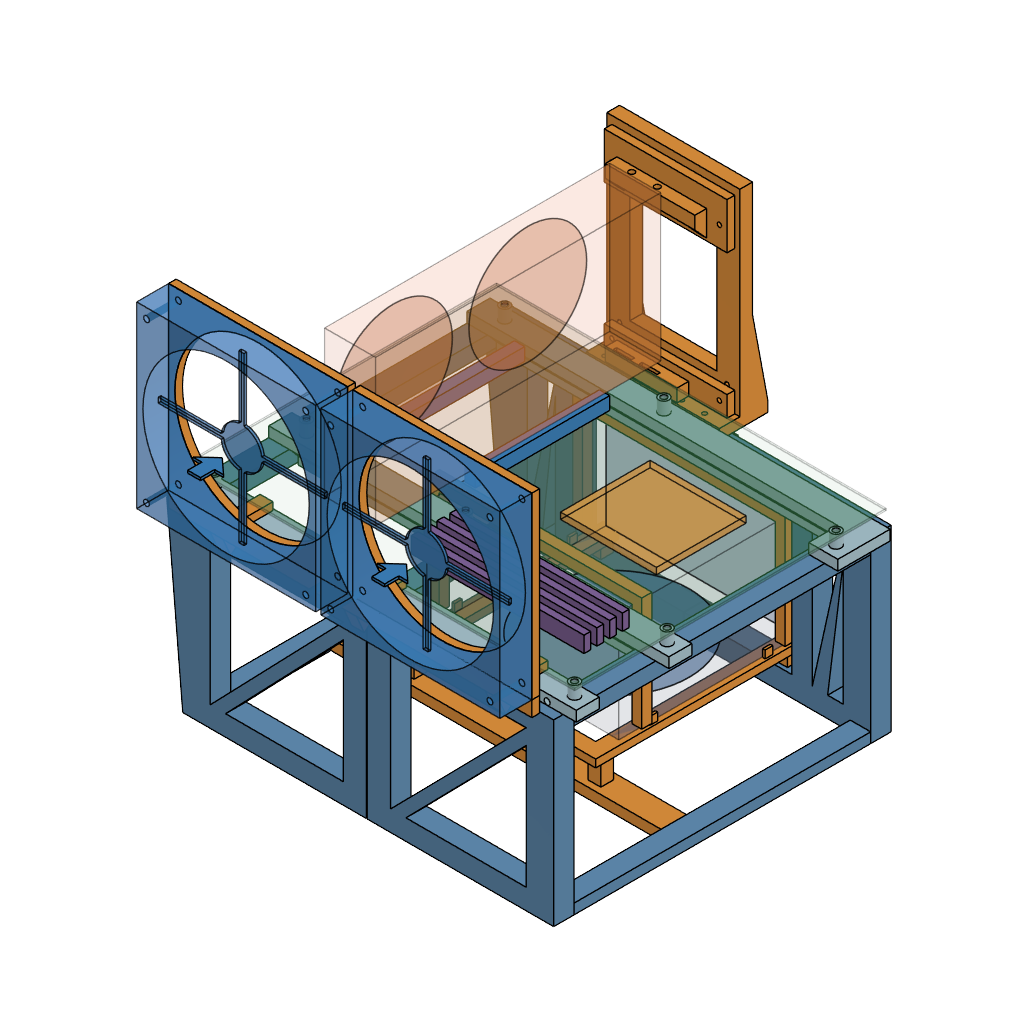
ATX_Desk_v08_layout (Autodesk Fusion 360 design; units mm, degrees)
part number: 2026-10-20-23-59-44-209
part number: 2026-10-20-23-59-51-964
part number: 2026-10-20-23-59-56-069
part number: 2026-10-21-00-00-01-103
part number: 2026-10-21-00-00-46-426
part number: 2026-10-21-00-00-56-981
part number: 2026-10-21-00-01-04-262
part number: 2026-10-21-00-01-12-035
part number: 2026-10-21-00-01-25-487
part number: 2026-10-21-00-01-28-371
part number: 2026-10-21-00-01-43-062
part number: 2026-10-21-00-01-46-190
part number: 2026-10-21-00-02-02-158
part number: 2026-10-21-00-02-04-809
part number: 2026-10-21-00-02-14-600
part number: 2026-10-21-00-02-17-363
part number: 2026-10-21-00-02-20-116
part number: 2026-10-21-00-02-27-737
part number: 2026-10-21-07-09-29-613
part number: 2026-10-21-07-09-34-403
part number: 2026-10-21-07-09-39-275
part number: 2026-10-21-07-09-42-839
part number: 2026-10-21-07-09-45-395
part number: 2026-10-21-07-15-53-070
part number: 2026-10-21-07-16-00-584
part number: 2026-10-21-07-16-09-777
part number: 2026-10-21-07-16-14-749
part number: 2026-10-21-07-16-20-002
part number: 2026-10-21-07-16-22-889
part number: 2026-10-21-07-16-25-682
part number: 2026-10-21-07-16-28-506
part number: 2026-10-21-07-23-00-483
part number: 2026-10-21-07-23-51-474
part number: 2026-10-21-07-24-11-185
part number: 2026-10-21-07-39-56-923
part number: 2026-10-21-07-40-00-193
part number: 2026-10-21-07-40-45-771
part number: 2026-10-21-07-40-57-754
Autodesk Fusion 360 part; units mm, degrees
(part 1 of 2)
ref_plane "工作平面1" through (0, 0, 190) normal (0, 0, 1) x (1, 0, 0) in component "03_FRONT_MOTHERBOARD_BEAM"
sketch "草图1" plane through (0, 0, 190) normal (0, 0, 1) x (1, 0, 0) in component "03_FRONT_MOTHERBOARD_BEAM"
  line L0 (-4, -2.65) -> (308.8, -2.65)
  line L1 (308.8, -2.65) -> (308.8, 15.35)
  line L2 (308.8, 15.35) -> (-4, 15.35)
  line L3 (-4, 15.35) -> (-4, -2.65)
extrude "Upper beam flange" add sketch "草图1" along normal blind 8 makes body 1 in component "03_FRONT_MOTHERBOARD_BEAM"
ref_plane "工作平面2" through (0, 0, 178) normal (0, 0, 1) x (1, 0, 0) in component "03_FRONT_MOTHERBOARD_BEAM"
sketch "草图2" plane through (0, 0, 178) normal (0, 0, 1) x (1, 0, 0) in component "03_FRONT_MOTHERBOARD_BEAM"
  line L0 (14, 2.35) -> (281.45, 2.35)
  line L1 (281.45, 2.35) -> (281.45, 10.35)
  line L2 (281.45, 10.35) -> (14, 10.35)
  line L3 (14, 10.35) -> (14, 2.35)
extrude "Underside rib" add sketch "草图2" along normal blind 12 bodies 1 in component "03_FRONT_MOTHERBOARD_BEAM"
ref_plane "工作平面3" through (14, 0, 0) normal (1, 0, 0) x (0, 1, 0) in component "03_FRONT_MOTHERBOARD_BEAM"
sketch "草图3" plane through (14, 0, 0) normal (1, 0, 0) x (0, 0, -1) in component "03_FRONT_MOTHERBOARD_BEAM"
  line L0 (-184, 2.35) -> (-184, 10.35)
  line L1 (-184, 10.35) -> (-190, 15.35)
  line L2 (-190, 15.35) -> (-190, -2.65)
  line L3 (-190, -2.65) -> (-184, 2.35)
extrude "Printable rib transition" add sketch "草图3" along normal blind 267.45 bodies 1 in component "03_FRONT_MOTHERBOARD_BEAM"
ref_plane "工作平面4" through (0, 0, 198) normal (0, 0, 1) x (1, 0, 0) in component "03_FRONT_MOTHERBOARD_BEAM"
sketch "草图4" plane through (0, 0, 198) normal (0, 0, 1) x (1, 0, 0) in component "03_FRONT_MOTHERBOARD_BEAM"
  circle A0 centre (16.51, 6.35) radius 4
extrude "Motherboard mount 7" add sketch "草图4" along normal blind 10 bodies 1 in component "03_FRONT_MOTHERBOARD_BEAM"
ref_plane "工作平面5" through (0, 0, 203.1) normal (0, 0, 1) x (1, 0, 0) in component "03_FRONT_MOTHERBOARD_BEAM"
sketch "草图5" plane through (0, 0, 203.1) normal (0, 0, 1) x (1, 0, 0) in component "03_FRONT_MOTHERBOARD_BEAM"
  circle A0 centre (16.51, 6.35) radius 2.35
extrude "M3 insert pocket 7" cut sketch "草图5" along normal blind 4.9 bodies 1 in component "03_FRONT_MOTHERBOARD_BEAM"
ref_plane "工作平面6" through (0, 0, 198) normal (0, 0, 1) x (1, 0, 0) in component "03_FRONT_MOTHERBOARD_BEAM"
sketch "草图6" plane through (0, 0, 198) normal (0, 0, 1) x (1, 0, 0) in component "03_FRONT_MOTHERBOARD_BEAM"
  circle A0 centre (140.97, 6.35) radius 4
extrude "Motherboard mount 8" add sketch "草图6" along normal blind 10 bodies 1 in component "03_FRONT_MOTHERBOARD_BEAM"
ref_plane "工作平面7" through (0, 0, 203.1) normal (0, 0, 1) x (1, 0, 0) in component "03_FRONT_MOTHERBOARD_BEAM"
sketch "草图7" plane through (0, 0, 203.1) normal (0, 0, 1) x (1, 0, 0) in component "03_FRONT_MOTHERBOARD_BEAM"
  circle A0 centre (140.97, 6.35) radius 2.35
extrude "M3 insert pocket 8" cut sketch "草图7" along normal blind 4.9 bodies 1 in component "03_FRONT_MOTHERBOARD_BEAM"
ref_plane "工作平面8" through (0, 0, 198) normal (0, 0, 1) x (1, 0, 0) in component "03_FRONT_MOTHERBOARD_BEAM"
sketch "草图8" plane through (0, 0, 198) normal (0, 0, 1) x (1, 0, 0) in component "03_FRONT_MOTHERBOARD_BEAM"
  circle A0 centre (298.45, 6.35) radius 4
extrude "Motherboard mount 9" add sketch "草图8" along normal blind 10 bodies 1 in component "03_FRONT_MOTHERBOARD_BEAM"
ref_plane "工作平面9" through (0, 0, 203.1) normal (0, 0, 1) x (1, 0, 0) in component "03_FRONT_MOTHERBOARD_BEAM"
sketch "草图9" plane through (0, 0, 203.1) normal (0, 0, 1) x (1, 0, 0) in component "03_FRONT_MOTHERBOARD_BEAM"
  circle A0 centre (298.45, 6.35) radius 2.35
extrude "M3 insert pocket 9" cut sketch "草图9" along normal blind 4.9 bodies 1 in component "03_FRONT_MOTHERBOARD_BEAM"
ref_plane "工作平面1" through (0, 0, 190) normal (0, 0, 1) x (1, 0, 0) in component "03_MID_MOTHERBOARD_BEAM"
sketch "草图1 (2)" plane through (0, 0, 190) normal (0, 0, 1) x (1, 0, 0) in component "03_MID_MOTHERBOARD_BEAM"
  line L0 (-4, 69.74) -> (308.8, 69.74)
  line L1 (308.8, 69.74) -> (308.8, 87.74)
  line L2 (308.8, 87.74) -> (-4, 87.74)
  line L3 (-4, 87.74) -> (-4, 69.74)
extrude "Upper beam flange'" add sketch "草图1 (2)" along normal blind 8 separate body makes body 2 in component "03_MID_MOTHERBOARD_BEAM"
ref_plane "工作平面2" through (0, 0, 178) normal (0, 0, 1) x (1, 0, 0) in component "03_MID_MOTHERBOARD_BEAM"
sketch "草图2 (2)" plane through (0, 0, 178) normal (0, 0, 1) x (1, 0, 0) in component "03_MID_MOTHERBOARD_BEAM"
  line L0 (14, 74.74) -> (281.45, 74.74)
  line L1 (281.45, 74.74) -> (281.45, 82.74)
  line L2 (281.45, 82.74) -> (14, 82.74)
  line L3 (14, 82.74) -> (14, 74.74)
extrude "Underside rib'" add sketch "草图2 (2)" along normal blind 12 bodies 2 in component "03_MID_MOTHERBOARD_BEAM"
ref_plane "工作平面3" through (14, 0, 0) normal (1, 0, 0) x (0, 1, 0) in component "03_MID_MOTHERBOARD_BEAM"
sketch "草图3 (2)" plane through (14, 0, 0) normal (1, 0, 0) x (0, 0, -1) in component "03_MID_MOTHERBOARD_BEAM"
  line L0 (-184, 74.74) -> (-184, 82.74)
  line L1 (-184, 82.74) -> (-190, 87.74)
  line L2 (-190, 87.74) -> (-190, 69.74)
  line L3 (-190, 69.74) -> (-184, 74.74)
extrude "Printable rib transition'" add sketch "草图3 (2)" along normal blind 267.45 bodies 2 in component "03_MID_MOTHERBOARD_BEAM"
ref_plane "工作平面4" through (0, 0, 198) normal (0, 0, 1) x (1, 0, 0) in component "03_MID_MOTHERBOARD_BEAM"
sketch "草图4 (2)" plane through (0, 0, 198) normal (0, 0, 1) x (1, 0, 0) in component "03_MID_MOTHERBOARD_BEAM"
  circle A0 centre (16.51, 78.74) radius 4
extrude "Motherboard mount 4" add sketch "草图4 (2)" along normal blind 10 bodies 2 in component "03_MID_MOTHERBOARD_BEAM"
ref_plane "工作平面5" through (0, 0, 203.1) normal (0, 0, 1) x (1, 0, 0) in component "03_MID_MOTHERBOARD_BEAM"
sketch "草图5 (2)" plane through (0, 0, 203.1) normal (0, 0, 1) x (1, 0, 0) in component "03_MID_MOTHERBOARD_BEAM"
  circle A0 centre (16.51, 78.74) radius 2.35
extrude "M3 insert pocket 4" cut sketch "草图5 (2)" along normal blind 4.9 bodies 2 in component "03_MID_MOTHERBOARD_BEAM"
ref_plane "工作平面6" through (0, 0, 198) normal (0, 0, 1) x (1, 0, 0) in component "03_MID_MOTHERBOARD_BEAM"
sketch "草图6 (2)" plane through (0, 0, 198) normal (0, 0, 1) x (1, 0, 0) in component "03_MID_MOTHERBOARD_BEAM"
  circle A0 centre (140.97, 78.74) radius 4
extrude "Motherboard mount 5" add sketch "草图6 (2)" along normal blind 10 bodies 2 in component "03_MID_MOTHERBOARD_BEAM"
ref_plane "工作平面7" through (0, 0, 203.1) normal (0, 0, 1) x (1, 0, 0) in component "03_MID_MOTHERBOARD_BEAM"
sketch "草图7 (2)" plane through (0, 0, 203.1) normal (0, 0, 1) x (1, 0, 0) in component "03_MID_MOTHERBOARD_BEAM"
  circle A0 centre (140.97, 78.74) radius 2.35
extrude "M3 insert pocket 5" cut sketch "草图7 (2)" along normal blind 4.9 bodies 2 in component "03_MID_MOTHERBOARD_BEAM"
ref_plane "工作平面8" through (0, 0, 198) normal (0, 0, 1) x (1, 0, 0) in component "03_MID_MOTHERBOARD_BEAM"
sketch "草图8 (2)" plane through (0, 0, 198) normal (0, 0, 1) x (1, 0, 0) in component "03_MID_MOTHERBOARD_BEAM"
  circle A0 centre (298.45, 78.74) radius 4
extrude "Motherboard mount 6" add sketch "草图8 (2)" along normal blind 10 bodies 2 in component "03_MID_MOTHERBOARD_BEAM"
ref_plane "工作平面9" through (0, 0, 203.1) normal (0, 0, 1) x (1, 0, 0) in component "03_MID_MOTHERBOARD_BEAM"
sketch "草图9 (2)" plane through (0, 0, 203.1) normal (0, 0, 1) x (1, 0, 0) in component "03_MID_MOTHERBOARD_BEAM"
  circle A0 centre (298.45, 78.74) radius 2.35
extrude "M3 insert pocket 6" cut sketch "草图9 (2)" along normal blind 4.9 bodies 2 in component "03_MID_MOTHERBOARD_BEAM"
ref_plane "工作平面1" through (0, 0, 190) normal (0, 0, 1) x (1, 0, 0) in component "03_REAR_MOTHERBOARD_BEAM"
sketch "草图1 (3)" plane through (0, 0, 190) normal (0, 0, 1) x (1, 0, 0) in component "03_REAR_MOTHERBOARD_BEAM"
  line L0 (-4, 224.68) -> (308.8, 224.68)
  line L1 (308.8, 224.68) -> (308.8, 242.68)
  line L2 (308.8, 242.68) -> (-4, 242.68)
  line L3 (-4, 242.68) -> (-4, 224.68)
extrude "Upper beam flange''" add sketch "草图1 (3)" along normal blind 8 separate body makes body 3 in component "03_REAR_MOTHERBOARD_BEAM"
ref_plane "工作平面2" through (0, 0, 178) normal (0, 0, 1) x (1, 0, 0) in component "03_REAR_MOTHERBOARD_BEAM"
sketch "草图2 (3)" plane through (0, 0, 178) normal (0, 0, 1) x (1, 0, 0) in component "03_REAR_MOTHERBOARD_BEAM"
  line L0 (14, 229.68) -> (281.45, 229.68)
  line L1 (281.45, 229.68) -> (281.45, 237.68)
  line L2 (281.45, 237.68) -> (14, 237.68)
  line L3 (14, 237.68) -> (14, 229.68)
extrude "Underside rib''" add sketch "草图2 (3)" along normal blind 12 bodies 3 in component "03_REAR_MOTHERBOARD_BEAM"
ref_plane "工作平面3" through (14, 0, 0) normal (1, 0, 0) x (0, 1, 0) in component "03_REAR_MOTHERBOARD_BEAM"
sketch "草图3 (3)" plane through (14, 0, 0) normal (1, 0, 0) x (0, 0, -1) in component "03_REAR_MOTHERBOARD_BEAM"
  line L0 (-184, 229.68) -> (-184, 237.68)
  line L1 (-184, 237.68) -> (-190, 242.68)
  line L2 (-190, 242.68) -> (-190, 224.68)
  line L3 (-190, 224.68) -> (-184, 229.68)
extrude "Printable rib transition''" add sketch "草图3 (3)" along normal blind 267.45 bodies 3 in component "03_REAR_MOTHERBOARD_BEAM"
ref_plane "工作平面4" through (0, 0, 190) normal (0, 0, 1) x (1, 0, 0) in component "03_REAR_MOTHERBOARD_BEAM"
sketch "草图4 (3)" plane through (0, 0, 190) normal (0, 0, 1) x (1, 0, 0) in component "03_REAR_MOTHERBOARD_BEAM"
  line L0 (286, 201.82) -> (308.8, 201.82)
  line L1 (308.8, 201.82) -> (308.8, 233.68)
  line L2 (308.8, 233.68) -> (286, 233.68)
  line L3 (286, 233.68) -> (286, 201.82)
extrude "Staggered hole 3 pad" add sketch "草图4 (3)" along normal blind 8 bodies 3 in component "03_REAR_MOTHERBOARD_BEAM"
ref_plane "工作平面5" through (0, 0, 198) normal (0, 0, 1) x (1, 0, 0) in component "03_REAR_MOTHERBOARD_BEAM"
sketch "草图5 (3)" plane through (0, 0, 198) normal (0, 0, 1) x (1, 0, 0) in component "03_REAR_MOTHERBOARD_BEAM"
  circle A0 centre (16.51, 233.68) radius 4
extrude "Motherboard mount 1" add sketch "草图5 (3)" along normal blind 10 bodies 3 in component "03_REAR_MOTHERBOARD_BEAM"
ref_plane "工作平面6" through (0, 0, 203.1) normal (0, 0, 1) x (1, 0, 0) in component "03_REAR_MOTHERBOARD_BEAM"
sketch "草图6 (3)" plane through (0, 0, 203.1) normal (0, 0, 1) x (1, 0, 0) in component "03_REAR_MOTHERBOARD_BEAM"
  circle A0 centre (16.51, 233.68) radius 2.35
extrude "M3 insert pocket 1" cut sketch "草图6 (3)" along normal blind 4.9 bodies 3 in component "03_REAR_MOTHERBOARD_BEAM"
ref_plane "工作平面7" through (0, 0, 198) normal (0, 0, 1) x (1, 0, 0) in component "03_REAR_MOTHERBOARD_BEAM"
sketch "草图7 (3)" plane through (0, 0, 198) normal (0, 0, 1) x (1, 0, 0) in component "03_REAR_MOTHERBOARD_BEAM"
  circle A0 centre (140.97, 233.68) radius 4
extrude "Motherboard mount 2" add sketch "草图7 (3)" along normal blind 10 bodies 3 in component "03_REAR_MOTHERBOARD_BEAM"
ref_plane "工作平面8" through (0, 0, 203.1) normal (0, 0, 1) x (1, 0, 0) in component "03_REAR_MOTHERBOARD_BEAM"
sketch "草图8 (3)" plane through (0, 0, 203.1) normal (0, 0, 1) x (1, 0, 0) in component "03_REAR_MOTHERBOARD_BEAM"
  circle A0 centre (140.97, 233.68) radius 2.35
extrude "M3 insert pocket 2" cut sketch "草图8 (3)" along normal blind 4.9 bodies 3 in component "03_REAR_MOTHERBOARD_BEAM"
ref_plane "工作平面9" through (0, 0, 198) normal (0, 0, 1) x (1, 0, 0) in component "03_REAR_MOTHERBOARD_BEAM"
sketch "草图9 (3)" plane through (0, 0, 198) normal (0, 0, 1) x (1, 0, 0) in component "03_REAR_MOTHERBOARD_BEAM"
  circle A0 centre (298.45, 210.82) radius 4
extrude "Motherboard mount 3" add sketch "草图9 (3)" along normal blind 10 bodies 3 in component "03_REAR_MOTHERBOARD_BEAM"
ref_plane "工作平面10" through (0, 0, 203.1) normal (0, 0, 1) x (1, 0, 0) in component "03_REAR_MOTHERBOARD_BEAM"
sketch "草图10" plane through (0, 0, 203.1) normal (0, 0, 1) x (1, 0, 0) in component "03_REAR_MOTHERBOARD_BEAM"
  circle A0 centre (298.45, 210.82) radius 2.35
extrude "M3 insert pocket 3" cut sketch "草图10" along normal blind 4.9 bodies 3 in component "03_REAR_MOTHERBOARD_BEAM"
ref_plane "工作平面1" through (0, 0, 198) normal (0, 0, 1) x (1, 0, 0) in component "09_FRONT_DUAL_FAN_CARRIER"
sketch "草图1 (4)" plane through (0, 0, 198) normal (0, 0, 1) x (1, 0, 0) in component "09_FRONT_DUAL_FAN_CARRIER"
  line L0 (12.4, -25) -> (296.4, -25)
  line L1 (296.4, -25) -> (296.4, -19)
  line L2 (296.4, -19) -> (12.4, -19)
  line L3 (12.4, -19) -> (12.4, -25)
extrude "Common 284 mm wide fan carrier" add sketch "草图1 (4)" along normal blind 12 separate body makes body 4 in component "09_FRONT_DUAL_FAN_CARRIER"
ref_plane "工作平面2" through (0, 0, 198) normal (0, 0, 1) x (1, 0, 0) in component "09_FRONT_DUAL_FAN_CARRIER"
sketch "草图2 (4)" plane through (0, 0, 198) normal (0, 0, 1) x (1, 0, 0) in component "09_FRONT_DUAL_FAN_CARRIER"
  line L0 (45, -19) -> (55, -19)
  line L1 (55, -19) -> (55, 14)
  line L2 (55, 14) -> (45, 14)
  line L3 (45, 14) -> (45, -19)
extrude "Fan carrier arm onto front beam" add sketch "草图2 (4)" along normal blind 6 bodies 4 in component "09_FRONT_DUAL_FAN_CARRIER"
ref_plane "工作平面3" through (45, 0, 0) normal (1, 0, 0) x (0, 1, 0) in component "09_FRONT_DUAL_FAN_CARRIER"
sketch "草图3 (4)" plane through (45, 0, 0) normal (1, 0, 0) x (0, 0, -1) in component "09_FRONT_DUAL_FAN_CARRIER"
  line L0 (-198, -25) -> (-184, -19)
  line L1 (-184, -19) -> (-198, -2.65)
  line L2 (-198, -2.65) -> (-198, -25)
extrude "Fan carrier arm gusset" add sketch "草图3 (4)" along normal blind 10 bodies 4 in component "09_FRONT_DUAL_FAN_CARRIER"
ref_plane "工作平面4" through (0, 0, 198) normal (0, 0, 1) x (1, 0, 0) in component "09_FRONT_DUAL_FAN_CARRIER"
sketch "草图4 (4)" plane through (0, 0, 198) normal (0, 0, 1) x (1, 0, 0) in component "09_FRONT_DUAL_FAN_CARRIER"
  line L0 (149.4, -19) -> (159.4, -19)
  line L1 (159.4, -19) -> (159.4, 14)
  line L2 (159.4, 14) -> (149.4, 14)
  line L3 (149.4, 14) -> (149.4, -19)
extrude "Fan carrier arm onto front beam (1)" add sketch "草图4 (4)" along normal blind 6 bodies 4 in component "09_FRONT_DUAL_FAN_CARRIER"
ref_plane "工作平面5" through (149.4, 0, 0) normal (1, 0, 0) x (0, 1, 0) in component "09_FRONT_DUAL_FAN_CARRIER"
sketch "草图5 (4)" plane through (149.4, 0, 0) normal (1, 0, 0) x (0, 0, -1) in component "09_FRONT_DUAL_FAN_CARRIER"
  line L0 (-198, -25) -> (-184, -19)
  line L1 (-184, -19) -> (-198, -2.65)
  line L2 (-198, -2.65) -> (-198, -25)
extrude "Fan carrier arm gusset (1)" add sketch "草图5 (4)" along normal blind 10 bodies 4 in component "09_FRONT_DUAL_FAN_CARRIER"
ref_plane "工作平面6" through (0, 0, 198) normal (0, 0, 1) x (1, 0, 0) in component "09_FRONT_DUAL_FAN_CARRIER"
sketch "草图6 (4)" plane through (0, 0, 198) normal (0, 0, 1) x (1, 0, 0) in component "09_FRONT_DUAL_FAN_CARRIER"
  line L0 (260, -19) -> (270, -19)
  line L1 (270, -19) -> (270, 14)
  line L2 (270, 14) -> (260, 14)
  line L3 (260, 14) -> (260, -19)
extrude "Fan carrier arm onto front beam (2)" add sketch "草图6 (4)" along normal blind 6 bodies 4 in component "09_FRONT_DUAL_FAN_CARRIER"
ref_plane "工作平面7" through (260, 0, 0) normal (1, 0, 0) x (0, 1, 0) in component "09_FRONT_DUAL_FAN_CARRIER"
sketch "草图7 (4)" plane through (260, 0, 0) normal (1, 0, 0) x (0, 0, -1) in component "09_FRONT_DUAL_FAN_CARRIER"
  line L0 (-198, -25) -> (-184, -19)
  line L1 (-184, -19) -> (-198, -2.65)
  line L2 (-198, -2.65) -> (-198, -25)
extrude "Fan carrier arm gusset (2)" add sketch "草图7 (4)" along normal blind 10 bodies 4 in component "09_FRONT_DUAL_FAN_CARRIER"
ref_plane "工作平面1" through (0, 25, 0) normal (0, 1, 0) x (0, 0, 1) in component "10_GPU_140_FAN_MOUNT"
sketch "草图1 (5)" plane through (0, 25, 0) normal (0, 1, 0) x (1, 0, 0) in component "10_GPU_140_FAN_MOUNT"
  line L0 (12.4, -210, -50) -> (152.4, -210, -50)
  line L1 (152.4, -210, -50) -> (152.4, -350, -50)
  line L2 (152.4, -350, -50) -> (12.4, -350, -50)
  line L3 (12.4, -350, -50) -> (12.4, -210, -50)
extrude "140 mm removable fan mounting frame" add sketch "草图1 (5)" along normal blind 6 separate body contours L0 L1 L2 L3 in plane through (0, -25, 0) normal (0, 1, 0) makes body 5 in component "10_GPU_140_FAN_MOUNT"
ref_plane "工作平面2" through (0, 25, 0) normal (0, 1, 0) x (0, 0, 1) in component "10_GPU_140_FAN_MOUNT"
sketch "草图2 (5)" plane through (0, 25, 0) normal (0, 1, 0) x (1, 0, 0) in component "10_GPU_140_FAN_MOUNT"
  circle A0 through (147.4, -280, -50) (49.9, -223.7083, -50) (49.9, -336.2917, -50)
extrude "Open airflow aperture" cut sketch "草图2 (5)" along normal blind 6 contours A0 in plane through (0, -25, 0) normal (0, 1, 0) bodies 5 in component "10_GPU_140_FAN_MOUNT"
ref_plane "工作平面3" through (0, 25, 0) normal (0, 1, 0) x (0, 0, 1) in component "10_GPU_140_FAN_MOUNT"
sketch "草图3 (5)" plane through (0, 25, 0) normal (0, 1, 0) x (1, 0, 0) in component "10_GPU_140_FAN_MOUNT"
  circle A0 through (22.4, -217.75, -50) (19.025, -215.8014, -50) (19.025, -219.6986, -50)
extrude "124.5 mm pitch fan fixing clearance" cut sketch "草图3 (5)" along normal blind 6 contours A0 in plane through (0, -25, 0) normal (0, 1, 0) bodies 5 in component "10_GPU_140_FAN_MOUNT"
ref_plane "工作平面4" through (0, 25, 0) normal (0, 1, 0) x (0, 0, 1) in component "10_GPU_140_FAN_MOUNT"
sketch "草图4 (5)" plane through (0, 25, 0) normal (0, 1, 0) x (1, 0, 0) in component "10_GPU_140_FAN_MOUNT"
  circle A0 through (22.4, -342.25, -50) (19.025, -340.3014, -50) (19.025, -344.1986, -50)
extrude "124.5 mm pitch fan fixing clearance (1)" cut sketch "草图4 (5)" along normal blind 6 contours A0 in plane through (0, -25, 0) normal (0, 1, 0) bodies 5 in component "10_GPU_140_FAN_MOUNT"
ref_plane "工作平面5" through (0, 25, 0) normal (0, 1, 0) x (0, 0, 1) in component "10_GPU_140_FAN_MOUNT"
sketch "草图5 (5)" plane through (0, 25, 0) normal (0, 1, 0) x (1, 0, 0) in component "10_GPU_140_FAN_MOUNT"
  circle A0 through (146.9, -217.75, -50) (143.525, -215.8014, -50) (143.525, -219.6986, -50)
extrude "124.5 mm pitch fan fixing clearance (2)" cut sketch "草图5 (5)" along normal blind 6 contours A0 in plane through (0, -25, 0) normal (0, 1, 0) bodies 5 in component "10_GPU_140_FAN_MOUNT"
ref_plane "工作平面6" through (0, 25, 0) normal (0, 1, 0) x (0, 0, 1) in component "10_GPU_140_FAN_MOUNT"
sketch "草图6 (5)" plane through (0, 25, 0) normal (0, 1, 0) x (1, 0, 0) in component "10_GPU_140_FAN_MOUNT"
  circle A0 through (146.9, -342.25, -50) (143.525, -340.3014, -50) (143.525, -344.1986, -50)
extrude "124.5 mm pitch fan fixing clearance (3)" cut sketch "草图6 (5)" along normal blind 6 contours A0 in plane through (0, -25, 0) normal (0, 1, 0) bodies 5 in component "10_GPU_140_FAN_MOUNT"
ref_plane "工作平面1" through (0, 25, 0) normal (0, 1, 0) x (0, 0, 1) in component "10_CPU_140_FAN_MOUNT"
sketch "草图1 (6)" plane through (0, 25, 0) normal (0, 1, 0) x (1, 0, 0) in component "10_CPU_140_FAN_MOUNT"
  line L0 (156.4, -210, -50) -> (296.4, -210, -50)
  line L1 (296.4, -210, -50) -> (296.4, -350, -50)
  line L2 (296.4, -350, -50) -> (156.4, -350, -50)
  line L3 (156.4, -350, -50) -> (156.4, -210, -50)
extrude "140 mm removable fan mounting frame'" add sketch "草图1 (6)" along normal blind 6 separate body contours L0 L1 L2 L3 in plane through (0, -25, 0) normal (0, 1, 0) makes body 6 in component "10_CPU_140_FAN_MOUNT"
ref_plane "工作平面2" through (0, 25, 0) normal (0, 1, 0) x (0, 0, 1) in component "10_CPU_140_FAN_MOUNT"
sketch "草图2 (6)" plane through (0, 25, 0) normal (0, 1, 0) x (1, 0, 0) in component "10_CPU_140_FAN_MOUNT"
  circle A0 through (291.4, -280, -50) (193.9, -223.7083, -50) (193.9, -336.2917, -50)
extrude "Open airflow aperture'" cut sketch "草图2 (6)" along normal blind 6 contours A0 in plane through (0, -25, 0) normal (0, 1, 0) bodies 6 in component "10_CPU_140_FAN_MOUNT"
ref_plane "工作平面3" through (0, 25, 0) normal (0, 1, 0) x (0, 0, 1) in component "10_CPU_140_FAN_MOUNT"
sketch "草图3 (6)" plane through (0, 25, 0) normal (0, 1, 0) x (1, 0, 0) in component "10_CPU_140_FAN_MOUNT"
  circle A0 through (166.4, -217.75, -50) (163.025, -215.8014, -50) (163.025, -219.6986, -50)
extrude "124.5 mm pitch fan fixing clearance'" cut sketch "草图3 (6)" along normal blind 6 contours A0 in plane through (0, -25, 0) normal (0, 1, 0) bodies 6 in component "10_CPU_140_FAN_MOUNT"
ref_plane "工作平面4" through (0, 25, 0) normal (0, 1, 0) x (0, 0, 1) in component "10_CPU_140_FAN_MOUNT"
sketch "草图4 (6)" plane through (0, 25, 0) normal (0, 1, 0) x (1, 0, 0) in component "10_CPU_140_FAN_MOUNT"
  circle A0 through (166.4, -342.25, -50) (163.025, -340.3014, -50) (163.025, -344.1986, -50)
extrude "124.5 mm pitch fan fixing clearance (1)'" cut sketch "草图4 (6)" along normal blind 6 contours A0 in plane through (0, -25, 0) normal (0, 1, 0) bodies 6 in component "10_CPU_140_FAN_MOUNT"
ref_plane "工作平面5" through (0, 25, 0) normal (0, 1, 0) x (0, 0, 1) in component "10_CPU_140_FAN_MOUNT"
sketch "草图5 (6)" plane through (0, 25, 0) normal (0, 1, 0) x (1, 0, 0) in component "10_CPU_140_FAN_MOUNT"
  circle A0 through (290.9, -217.75, -50) (287.525, -215.8014, -50) (287.525, -219.6986, -50)
extrude "124.5 mm pitch fan fixing clearance (2)'" cut sketch "草图5 (6)" along normal blind 6 contours A0 in plane through (0, -25, 0) normal (0, 1, 0) bodies 6 in component "10_CPU_140_FAN_MOUNT"
ref_plane "工作平面6" through (0, 25, 0) normal (0, 1, 0) x (0, 0, 1) in component "10_CPU_140_FAN_MOUNT"
sketch "草图6 (6)" plane through (0, 25, 0) normal (0, 1, 0) x (1, 0, 0) in component "10_CPU_140_FAN_MOUNT"
  circle A0 through (290.9, -342.25, -50) (287.525, -340.3014, -50) (287.525, -344.1986, -50)
extrude "124.5 mm pitch fan fixing clearance (3)'" cut sketch "草图6 (6)" along normal blind 6 contours A0 in plane through (0, -25, 0) normal (0, 1, 0) bodies 6 in component "10_CPU_140_FAN_MOUNT"
ref_plane "工作平面1" through (0, 50, 0) normal (0, 1, 0) x (0, 0, 1) in component "REF_CASE_FAN_GPU_140x140x25"
sketch "草图1 (7)" plane through (0, 50, 0) normal (0, 1, 0) x (1, 0, 0) in component "REF_CASE_FAN_GPU_140x140x25"
  line L0 (12.4, -210, -100) -> (152.4, -210, -100)
  line L1 (152.4, -210, -100) -> (152.4, -350, -100)
  line L2 (152.4, -350, -100) -> (12.4, -350, -100)
  line L3 (12.4, -350, -100) -> (12.4, -210, -100)
extrude "140x140x25 fan envelope" add sketch "草图1 (7)" along normal blind 25 separate body contours L0 L1 L2 L3 in plane through (0, -50, 0) normal (0, 1, 0) makes body 7 in component "REF_CASE_FAN_GPU_140x140x25"
ref_plane "工作平面2" through (0, 50, 0) normal (0, 1, 0) x (0, 0, 1) in component "REF_CASE_FAN_GPU_140x140x25"
sketch "草图2 (7)" plane through (0, 50, 0) normal (0, 1, 0) x (1, 0, 0) in component "REF_CASE_FAN_GPU_140x140x25"
  circle A0 through (147.4, -280, -100) (49.9, -223.7083, -100) (49.9, -336.2917, -100)
extrude "Rotor opening reference" cut sketch "草图2 (7)" along normal blind 25 contours A0 in plane through (0, -50, 0) normal (0, 1, 0) bodies 7 in component "REF_CASE_FAN_GPU_140x140x25"
ref_plane "工作平面3" through (0, 0, 278) normal (0, 0, 1) x (1, 0, 0) in component "REF_CASE_FAN_GPU_140x140x25"
sketch "草图3 (7)" plane through (0, 0, 278) normal (0, 0, 1) x (1, 0, 0) in component "REF_CASE_FAN_GPU_140x140x25"
  line L0 (15.4, -38) -> (149.4, -38)
  line L1 (149.4, -38) -> (149.4, -36)
  line L2 (149.4, -36) -> (15.4, -36)
  line L3 (15.4, -36) -> (15.4, -38)
extrude "Rotor reference spoke horizontal" add sketch "草图3 (7)" along normal blind 4 bodies 7 in component "REF_CASE_FAN_GPU_140x140x25"
ref_plane "工作平面4" through (0, 0, 213) normal (0, 0, 1) x (1, 0, 0) in component "REF_CASE_FAN_GPU_140x140x25"
sketch "草图4 (7)" plane through (0, 0, 213) normal (0, 0, 1) x (1, 0, 0) in component "REF_CASE_FAN_GPU_140x140x25"
  line L0 (80.4, -38) -> (84.4, -38)
  line L1 (84.4, -38) -> (84.4, -36)
  line L2 (84.4, -36) -> (80.4, -36)
  line L3 (80.4, -36) -> (80.4, -38)
extrude "Rotor reference spoke vertical" add sketch "草图4 (7)" along normal blind 134 bodies 7 in component "REF_CASE_FAN_GPU_140x140x25"
ref_plane "工作平面5" through (0, 38, 0) normal (0, 1, 0) x (0, 0, 1) in component "REF_CASE_FAN_GPU_140x140x25"
sketch "草图5 (7)" plane through (0, 38, 0) normal (0, 1, 0) x (1, 0, 0) in component "REF_CASE_FAN_GPU_140x140x25"
  circle A0 through (98.4, -280, -76) (74.4, -266.1436, -76) (74.4, -293.8564, -76)
extrude "Fan hub reference" add sketch "草图5 (7)" along normal blind 2 contours A0 in plane through (0, -38, 0) normal (0, 1, 0) bodies 7 in component "REF_CASE_FAN_GPU_140x140x25"
ref_plane "工作平面6" through (0, 50, 0) normal (0, 1, 0) x (0, 0, 1) in component "REF_CASE_FAN_GPU_140x140x25"
sketch "草图6 (7)" plane through (0, 50, 0) normal (0, 1, 0) x (1, 0, 0) in component "REF_CASE_FAN_GPU_140x140x25"
  circle A0 through (22.4, -217.75, -100) (19.025, -215.8014, -100) (19.025, -219.6986, -100)
extrude "Reference fan mounting bore" cut sketch "草图6 (7)" along normal blind 25 contours A0 in plane through (0, -50, 0) normal (0, 1, 0) bodies 7 in component "REF_CASE_FAN_GPU_140x140x25"
ref_plane "工作平面7" through (0, 50, 0) normal (0, 1, 0) x (0, 0, 1) in component "REF_CASE_FAN_GPU_140x140x25"
sketch "草图7 (5)" plane through (0, 50, 0) normal (0, 1, 0) x (1, 0, 0) in component "REF_CASE_FAN_GPU_140x140x25"
  circle A0 through (22.4, -342.25, -100) (19.025, -340.3014, -100) (19.025, -344.1986, -100)
extrude "Reference fan mounting bore (1)" cut sketch "草图7 (5)" along normal blind 25 contours A0 in plane through (0, -50, 0) normal (0, 1, 0) bodies 7 in component "REF_CASE_FAN_GPU_140x140x25"
ref_plane "工作平面8" through (0, 50, 0) normal (0, 1, 0) x (0, 0, 1) in component "REF_CASE_FAN_GPU_140x140x25"
sketch "草图8 (4)" plane through (0, 50, 0) normal (0, 1, 0) x (1, 0, 0) in component "REF_CASE_FAN_GPU_140x140x25"
  circle A0 through (146.9, -217.75, -100) (143.525, -215.8014, -100) (143.525, -219.6986, -100)
extrude "Reference fan mounting bore (2)" cut sketch "草图8 (4)" along normal blind 25 contours A0 in plane through (0, -50, 0) normal (0, 1, 0) bodies 7 in component "REF_CASE_FAN_GPU_140x140x25"
ref_plane "工作平面9" through (0, 50, 0) normal (0, 1, 0) x (0, 0, 1) in component "REF_CASE_FAN_GPU_140x140x25"
sketch "草图9 (4)" plane through (0, 50, 0) normal (0, 1, 0) x (1, 0, 0) in component "REF_CASE_FAN_GPU_140x140x25"
  circle A0 through (146.9, -342.25, -100) (143.525, -340.3014, -100) (143.525, -344.1986, -100)
extrude "Reference fan mounting bore (3)" cut sketch "草图9 (4)" along normal blind 25 contours A0 in plane through (0, -50, 0) normal (0, 1, 0) bodies 7 in component "REF_CASE_FAN_GPU_140x140x25"
ref_plane "工作平面1" through (0, 0, 279) normal (0, 0, 1) x (1, 0, 0) in component "REF_AIRFLOW_GPU_FRONT_TO_REAR"
sketch "草图1 (8)" plane through (0, 0, 279) normal (0, 0, 1) x (1, 0, 0) in component "REF_AIRFLOW_GPU_FRONT_TO_REAR"
  line L0 (77.4, -75) -> (87.4, -75)
  line L1 (87.4, -75) -> (87.4, -64)
  line L2 (87.4, -64) -> (94.4, -64)
  line L3 (94.4, -64) -> (82.4, -53)
  line L4 (82.4, -53) -> (70.4, -64)
  line L5 (70.4, -64) -> (77.4, -64)
  line L6 (77.4, -64) -> (77.4, -75)
extrude "Front intake direction +Y" add sketch "草图1 (8)" along normal blind 2 separate body makes body 8 in component "REF_AIRFLOW_GPU_FRONT_TO_REAR"
ref_plane "工作平面1" through (0, 50, 0) normal (0, 1, 0) x (0, 0, 1) in component "REF_CASE_FAN_CPU_140x140x25"
sketch "草图1 (9)" plane through (0, 50, 0) normal (0, 1, 0) x (1, 0, 0) in component "REF_CASE_FAN_CPU_140x140x25"
  line L0 (156.4, -210, -100) -> (296.4, -210, -100)
  line L1 (296.4, -210, -100) -> (296.4, -350, -100)
  line L2 (296.4, -350, -100) -> (156.4, -350, -100)
  line L3 (156.4, -350, -100) -> (156.4, -210, -100)
extrude "140x140x25 fan envelope'" add sketch "草图1 (9)" along normal blind 25 separate body contours L0 L1 L2 L3 in plane through (0, -50, 0) normal (0, 1, 0) makes body 9 in component "REF_CASE_FAN_CPU_140x140x25"
ref_plane "工作平面2" through (0, 50, 0) normal (0, 1, 0) x (0, 0, 1) in component "REF_CASE_FAN_CPU_140x140x25"
sketch "草图2 (8)" plane through (0, 50, 0) normal (0, 1, 0) x (1, 0, 0) in component "REF_CASE_FAN_CPU_140x140x25"
  circle A0 through (291.4, -280, -100) (193.9, -223.7083, -100) (193.9, -336.2917, -100)
extrude "Rotor opening reference'" cut sketch "草图2 (8)" along normal blind 25 contours A0 in plane through (0, -50, 0) normal (0, 1, 0) bodies 9 in component "REF_CASE_FAN_CPU_140x140x25"
ref_plane "工作平面3" through (0, 0, 278) normal (0, 0, 1) x (1, 0, 0) in component "REF_CASE_FAN_CPU_140x140x25"
sketch "草图3 (8)" plane through (0, 0, 278) normal (0, 0, 1) x (1, 0, 0) in component "REF_CASE_FAN_CPU_140x140x25"
  line L0 (159.4, -38) -> (293.4, -38)
  line L1 (293.4, -38) -> (293.4, -36)
  line L2 (293.4, -36) -> (159.4, -36)
  line L3 (159.4, -36) -> (159.4, -38)
extrude "Rotor reference spoke horizontal'" add sketch "草图3 (8)" along normal blind 4 bodies 9 in component "REF_CASE_FAN_CPU_140x140x25"
ref_plane "工作平面4" through (0, 0, 213) normal (0, 0, 1) x (1, 0, 0) in component "REF_CASE_FAN_CPU_140x140x25"
sketch "草图4 (8)" plane through (0, 0, 213) normal (0, 0, 1) x (1, 0, 0) in component "REF_CASE_FAN_CPU_140x140x25"
  line L0 (224.4, -38) -> (228.4, -38)
  line L1 (228.4, -38) -> (228.4, -36)
  line L2 (228.4, -36) -> (224.4, -36)
  line L3 (224.4, -36) -> (224.4, -38)
extrude "Rotor reference spoke vertical'" add sketch "草图4 (8)" along normal blind 134 bodies 9 in component "REF_CASE_FAN_CPU_140x140x25"
ref_plane "工作平面5" through (0, 38, 0) normal (0, 1, 0) x (0, 0, 1) in component "REF_CASE_FAN_CPU_140x140x25"
sketch "草图5 (8)" plane through (0, 38, 0) normal (0, 1, 0) x (1, 0, 0) in component "REF_CASE_FAN_CPU_140x140x25"
  circle A0 through (242.4, -280, -76) (218.4, -266.1436, -76) (218.4, -293.8564, -76)
extrude "Fan hub reference'" add sketch "草图5 (8)" along normal blind 2 contours A0 in plane through (0, -38, 0) normal (0, 1, 0) bodies 9 in component "REF_CASE_FAN_CPU_140x140x25"
ref_plane "工作平面6" through (0, 50, 0) normal (0, 1, 0) x (0, 0, 1) in component "REF_CASE_FAN_CPU_140x140x25"
sketch "草图6 (8)" plane through (0, 50, 0) normal (0, 1, 0) x (1, 0, 0) in component "REF_CASE_FAN_CPU_140x140x25"
  circle A0 through (166.4, -217.75, -100) (163.025, -215.8014, -100) (163.025, -219.6986, -100)
extrude "Reference fan mounting bore'" cut sketch "草图6 (8)" along normal blind 25 contours A0 in plane through (0, -50, 0) normal (0, 1, 0) bodies 9 in component "REF_CASE_FAN_CPU_140x140x25"
ref_plane "工作平面7" through (0, 50, 0) normal (0, 1, 0) x (0, 0, 1) in component "REF_CASE_FAN_CPU_140x140x25"
sketch "草图7 (6)" plane through (0, 50, 0) normal (0, 1, 0) x (1, 0, 0) in component "REF_CASE_FAN_CPU_140x140x25"
  circle A0 through (166.4, -342.25, -100) (163.025, -340.3014, -100) (163.025, -344.1986, -100)
extrude "Reference fan mounting bore (1)'" cut sketch "草图7 (6)" along normal blind 25 contours A0 in plane through (0, -50, 0) normal (0, 1, 0) bodies 9 in component "REF_CASE_FAN_CPU_140x140x25"
ref_plane "工作平面8" through (0, 50, 0) normal (0, 1, 0) x (0, 0, 1) in component "REF_CASE_FAN_CPU_140x140x25"
sketch "草图8 (5)" plane through (0, 50, 0) normal (0, 1, 0) x (1, 0, 0) in component "REF_CASE_FAN_CPU_140x140x25"
  circle A0 through (290.9, -217.75, -100) (287.525, -215.8014, -100) (287.525, -219.6986, -100)
extrude "Reference fan mounting bore (2)'" cut sketch "草图8 (5)" along normal blind 25 contours A0 in plane through (0, -50, 0) normal (0, 1, 0) bodies 9 in component "REF_CASE_FAN_CPU_140x140x25"
ref_plane "工作平面9" through (0, 50, 0) normal (0, 1, 0) x (0, 0, 1) in component "REF_CASE_FAN_CPU_140x140x25"
sketch "草图9 (5)" plane through (0, 50, 0) normal (0, 1, 0) x (1, 0, 0) in component "REF_CASE_FAN_CPU_140x140x25"
  circle A0 through (290.9, -342.25, -100) (287.525, -340.3014, -100) (287.525, -344.1986, -100)
extrude "Reference fan mounting bore (3)'" cut sketch "草图9 (5)" along normal blind 25 contours A0 in plane through (0, -50, 0) normal (0, 1, 0) bodies 9 in component "REF_CASE_FAN_CPU_140x140x25"
ref_plane "工作平面1" through (0, 0, 279) normal (0, 0, 1) x (1, 0, 0) in component "REF_AIRFLOW_CPU_FRONT_TO_REAR"
sketch "草图1 (10)" plane through (0, 0, 279) normal (0, 0, 1) x (1, 0, 0) in component "REF_AIRFLOW_CPU_FRONT_TO_REAR"
  line L0 (221.4, -75) -> (231.4, -75)
  line L1 (231.4, -75) -> (231.4, -64)
  line L2 (231.4, -64) -> (238.4, -64)
  line L3 (238.4, -64) -> (226.4, -53)
  line L4 (226.4, -53) -> (214.4, -64)
  line L5 (214.4, -64) -> (221.4, -64)
  line L6 (221.4, -64) -> (221.4, -75)
extrude "Front intake direction +Y'" add sketch "草图1 (10)" along normal blind 2 separate body makes body 10 in component "REF_AIRFLOW_CPU_FRONT_TO_REAR"
ref_plane "工作平面1" through (0, 0, 208) normal (0, 0, 1) x (1, 0, 0) in component "REF_BOARD_304.8x243.84_NUMBERED_HOLES"
sketch "草图1 (11)" plane through (0, 0, 208) normal (0, 0, 1) x (1, 0, 0) in component "REF_BOARD_304.8x243.84_NUMBERED_HOLES"
  line L0 (0, 0) -> (304.8, 0)
  line L1 (304.8, 0) -> (304.8, 243.84)
  line L2 (304.8, 243.84) -> (0, 243.84)
  line L3 (0, 243.84) -> (0, 0)
extrude "Motherboard component-side reference" add sketch "草图1 (11)" along normal blind 1.6 separate body makes body 11 in component "REF_BOARD_304.8x243.84_NUMBERED_HOLES"
ref_plane "工作平面2" through (0, 0, 208) normal (0, 0, 1) x (1, 0, 0) in component "REF_BOARD_304.8x243.84_NUMBERED_HOLES"
sketch "草图2 (9)" plane through (0, 0, 208) normal (0, 0, 1) x (1, 0, 0) in component "REF_BOARD_304.8x243.84_NUMBERED_HOLES"
  circle A0 centre (16.51, 233.68) radius 1.98
extrude "Board hole 1" cut sketch "草图2 (9)" along normal blind 1.6 bodies 11 in component "REF_BOARD_304.8x243.84_NUMBERED_HOLES"
ref_plane "工作平面3" through (0, 0, 208) normal (0, 0, 1) x (1, 0, 0) in component "REF_BOARD_304.8x243.84_NUMBERED_HOLES"
sketch "草图3 (9)" plane through (0, 0, 208) normal (0, 0, 1) x (1, 0, 0) in component "REF_BOARD_304.8x243.84_NUMBERED_HOLES"
  circle A0 centre (140.97, 233.68) radius 1.98
extrude "Board hole 2" cut sketch "草图3 (9)" along normal blind 1.6 bodies 11 in component "REF_BOARD_304.8x243.84_NUMBERED_HOLES"
ref_plane "工作平面4" through (0, 0, 208) normal (0, 0, 1) x (1, 0, 0) in component "REF_BOARD_304.8x243.84_NUMBERED_HOLES"
sketch "草图4 (9)" plane through (0, 0, 208) normal (0, 0, 1) x (1, 0, 0) in component "REF_BOARD_304.8x243.84_NUMBERED_HOLES"
  circle A0 centre (298.45, 210.82) radius 1.98
extrude "Board hole 3" cut sketch "草图4 (9)" along normal blind 1.6 bodies 11 in component "REF_BOARD_304.8x243.84_NUMBERED_HOLES"
ref_plane "工作平面5" through (0, 0, 208) normal (0, 0, 1) x (1, 0, 0) in component "REF_BOARD_304.8x243.84_NUMBERED_HOLES"
sketch "草图5 (9)" plane through (0, 0, 208) normal (0, 0, 1) x (1, 0, 0) in component "REF_BOARD_304.8x243.84_NUMBERED_HOLES"
  circle A0 centre (16.51, 78.74) radius 1.98
extrude "Board hole 4" cut sketch "草图5 (9)" along normal blind 1.6 bodies 11 in component "REF_BOARD_304.8x243.84_NUMBERED_HOLES"
ref_plane "工作平面6" through (0, 0, 208) normal (0, 0, 1) x (1, 0, 0) in component "REF_BOARD_304.8x243.84_NUMBERED_HOLES"
sketch "草图6 (9)" plane through (0, 0, 208) normal (0, 0, 1) x (1, 0, 0) in component "REF_BOARD_304.8x243.84_NUMBERED_HOLES"
  circle A0 centre (140.97, 78.74) radius 1.98
extrude "Board hole 5" cut sketch "草图6 (9)" along normal blind 1.6 bodies 11 in component "REF_BOARD_304.8x243.84_NUMBERED_HOLES"
ref_plane "工作平面7" through (0, 0, 208) normal (0, 0, 1) x (1, 0, 0) in component "REF_BOARD_304.8x243.84_NUMBERED_HOLES"
sketch "草图7 (7)" plane through (0, 0, 208) normal (0, 0, 1) x (1, 0, 0) in component "REF_BOARD_304.8x243.84_NUMBERED_HOLES"
  circle A0 centre (298.45, 78.74) radius 1.98
extrude "Board hole 6" cut sketch "草图7 (7)" along normal blind 1.6 bodies 11 in component "REF_BOARD_304.8x243.84_NUMBERED_HOLES"
ref_plane "工作平面8" through (0, 0, 208) normal (0, 0, 1) x (1, 0, 0) in component "REF_BOARD_304.8x243.84_NUMBERED_HOLES"
sketch "草图8 (6)" plane through (0, 0, 208) normal (0, 0, 1) x (1, 0, 0) in component "REF_BOARD_304.8x243.84_NUMBERED_HOLES"
  circle A0 centre (16.51, 6.35) radius 1.98
extrude "Board hole 7" cut sketch "草图8 (6)" along normal blind 1.6 bodies 11 in component "REF_BOARD_304.8x243.84_NUMBERED_HOLES"
ref_plane "工作平面9" through (0, 0, 208) normal (0, 0, 1) x (1, 0, 0) in component "REF_BOARD_304.8x243.84_NUMBERED_HOLES"
sketch "草图9 (6)" plane through (0, 0, 208) normal (0, 0, 1) x (1, 0, 0) in component "REF_BOARD_304.8x243.84_NUMBERED_HOLES"
  circle A0 centre (140.97, 6.35) radius 1.98
extrude "Board hole 8" cut sketch "草图9 (6)" along normal blind 1.6 bodies 11 in component "REF_BOARD_304.8x243.84_NUMBERED_HOLES"
ref_plane "工作平面10" through (0, 0, 208) normal (0, 0, 1) x (1, 0, 0) in component "REF_BOARD_304.8x243.84_NUMBERED_HOLES"
sketch "草图10 (2)" plane through (0, 0, 208) normal (0, 0, 1) x (1, 0, 0) in component "REF_BOARD_304.8x243.84_NUMBERED_HOLES"
  circle A0 centre (298.45, 6.35) radius 1.98
extrude "Board hole 9" cut sketch "草图10 (2)" along normal blind 1.6 bodies 11 in component "REF_BOARD_304.8x243.84_NUMBERED_HOLES"
ref_plane "工作平面1" through (0, 0, 209.6) normal (0, 0, 1) x (1, 0, 0) in component "REF_CPU_RIGHT"
sketch "草图1 (12)" plane through (0, 0, 209.6) normal (0, 0, 1) x (1, 0, 0) in component "REF_CPU_RIGHT"
  line L0 (185, 108.84) -> (260, 108.84)
  line L1 (260, 108.84) -> (260, 178.84)
  line L2 (260, 178.84) -> (185, 178.84)
  line L3 (185, 178.84) -> (185, 108.84)
extrude "CPU position reference only" add sketch "草图1 (12)" along normal blind 5 separate body makes body 12 in component "REF_CPU_RIGHT"
ref_plane "工作平面1" through (0, 0, 209.6) normal (0, 0, 1) x (1, 0, 0) in component "REF_MEMORY_RIGHT_FRONT"
sketch "草图1 (13)" plane through (0, 0, 209.6) normal (0, 0, 1) x (1, 0, 0) in component "REF_MEMORY_RIGHT_FRONT"
  line L0 (150, 57.24) -> (285, 57.24)
  line L1 (285, 57.24) -> (285, 62.44)
  line L2 (285, 62.44) -> (150, 62.44)
  line L3 (150, 62.44) -> (150, 57.24)
extrude "DIMM position reference" add sketch "草图1 (13)" along normal blind 12.4 separate body makes body 13 in component "REF_MEMORY_RIGHT_FRONT"
ref_plane "工作平面2" through (0, 0, 209.6) normal (0, 0, 1) x (1, 0, 0) in component "REF_MEMORY_RIGHT_FRONT"
sketch "草图2 (10)" plane through (0, 0, 209.6) normal (0, 0, 1) x (1, 0, 0) in component "REF_MEMORY_RIGHT_FRONT"
  line L0 (150, 47.24) -> (285, 47.24)
  line L1 (285, 47.24) -> (285, 52.44)
  line L2 (285, 52.44) -> (150, 52.44)
  line L3 (150, 52.44) -> (150, 47.24)
extrude "DIMM position reference (1)" add sketch "草图2 (10)" along normal blind 12.4 separate body makes body 14 in component "REF_MEMORY_RIGHT_FRONT"
ref_plane "工作平面3" through (0, 0, 209.6) normal (0, 0, 1) x (1, 0, 0) in component "REF_MEMORY_RIGHT_FRONT"
sketch "草图3 (10)" plane through (0, 0, 209.6) normal (0, 0, 1) x (1, 0, 0) in component "REF_MEMORY_RIGHT_FRONT"
  line L0 (150, 37.24) -> (285, 37.24)
  line L1 (285, 37.24) -> (285, 42.44)
  line L2 (285, 42.44) -> (150, 42.44)
  line L3 (150, 42.44) -> (150, 37.24)
extrude "DIMM position reference (2)" add sketch "草图3 (10)" along normal blind 12.4 separate body makes body 15 in component "REF_MEMORY_RIGHT_FRONT"
ref_plane "工作平面4" through (0, 0, 209.6) normal (0, 0, 1) x (1, 0, 0) in component "REF_MEMORY_RIGHT_FRONT"
sketch "草图4 (10)" plane through (0, 0, 209.6) normal (0, 0, 1) x (1, 0, 0) in component "REF_MEMORY_RIGHT_FRONT"
  line L0 (150, 27.24) -> (285, 27.24)
  line L1 (285, 27.24) -> (285, 32.44)
  line L2 (285, 32.44) -> (150, 32.44)
  line L3 (150, 32.44) -> (150, 27.24)
extrude "DIMM position reference (3)" add sketch "草图4 (10)" along normal blind 12.4 separate body makes body 16 in component "REF_MEMORY_RIGHT_FRONT"
ref_plane "工作平面1" through (0, 0, 209.6) normal (0, 0, 1) x (1, 0, 0) in component "REF_PRIMARY_PCIE_X126.4_APPROX"
sketch "草图1 (14)" plane through (0, 0, 209.6) normal (0, 0, 1) x (1, 0, 0) in component "REF_PRIMARY_PCIE_X126.4_APPROX"
  line L0 (122.4, 96.84) -> (130.4, 96.84)
  line L1 (130.4, 96.84) -> (130.4, 201.84)
  line L2 (130.4, 201.84) -> (122.4, 201.84)
  line L3 (122.4, 201.84) -> (122.4, 96.84)
extrude "Primary GPU slot approximate" add sketch "草图1 (14)" along normal blind 10 separate body makes body 17 in component "REF_PRIMARY_PCIE_X126.4_APPROX"
ref_plane "工作平面1" through (0, 0, 209.6) normal (0, 0, 1) x (1, 0, 0) in component "REF_SECOND_LONG_PCIE_X60_APPROX"
sketch "草图1 (15)" plane through (0, 0, 209.6) normal (0, 0, 1) x (1, 0, 0) in component "REF_SECOND_LONG_PCIE_X60_APPROX"
  line L0 (56, 96.84) -> (64, 96.84)
  line L1 (64, 96.84) -> (64, 201.84)
  line L2 (64, 201.84) -> (56, 201.84)
  line L3 (56, 201.84) -> (56, 96.84)
extrude "Second long PCIe approximate" add sketch "草图1 (15)" along normal blind 10 separate body makes body 18 in component "REF_SECOND_LONG_PCIE_X60_APPROX"
ref_plane "工作平面1" through (0, 0, 221) normal (0, 0, 1) x (1, 0, 0) in component "REF_GPU_FANS_TO_MINUS_X"
sketch "草图1 (16)" plane through (0, 0, 221) normal (0, 0, 1) x (1, 0, 0) in component "REF_GPU_FANS_TO_MINUS_X"
  line L0 (88.4, 20.84) -> (128.4, 20.84)
  line L1 (128.4, 20.84) -> (128.4, 243.84)
  line L2 (128.4, 243.84) -> (88.4, 243.84)
  line L3 (88.4, 243.84) -> (88.4, 20.84)
extrude "GPU body 40 x 223 x 114" add sketch "草图1 (16)" along normal blind 114 separate body makes body 19 in component "REF_GPU_FANS_TO_MINUS_X"
ref_plane "工作平面1" through (88.1, 0, 0) normal (1, 0, 0) x (0, 1, 0) in component "REF_GPU_FAN_MARKERS_MINUS_X"
sketch "草图1 (17)" plane through (88.1, 0, 0) normal (1, 0, 0) x (0, 0, -1) in component "REF_GPU_FAN_MARKERS_MINUS_X"
  circle A0 centre (-278, 75) radius 46
extrude "GPU fan faces away from PSU fan" add sketch "草图1 (17)" along normal blind 0.3 separate body makes body 20 in component "REF_GPU_FAN_MARKERS_MINUS_X"
ref_plane "工作平面2" through (88.1, 0, 0) normal (1, 0, 0) x (0, 1, 0) in component "REF_GPU_FAN_MARKERS_MINUS_X"
sketch "草图2 (11)" plane through (88.1, 0, 0) normal (1, 0, 0) x (0, 0, -1) in component "REF_GPU_FAN_MARKERS_MINUS_X"
  circle A0 centre (-278, 180) radius 46
extrude "GPU fan faces away from PSU fan (1)" add sketch "草图2 (11)" along normal blind 0.3 separate body makes body 21 in component "REF_GPU_FAN_MARKERS_MINUS_X"
ref_plane "工作平面10" through (0, 2.65, 0) normal (0, 1, 0) x (0, 0, 1) in component "03_FRONT_MOTHERBOARD_BEAM"
sketch "草图10 (3)" plane through (0, 2.65, 0) normal (0, 1, 0) x (1, 0, 0) in component "03_FRONT_MOTHERBOARD_BEAM"
  circle A0 through (27.35, -192.5, -5.3) (23.825, -190.4648, -5.3) (23.825, -194.5352, -5.3)
extrude "M3 short heat insert for removable front cover" cut sketch "草图10 (3)" along normal blind 4.7 contours A0 in plane through (0, -2.65, 0) normal (0, 1, 0) bodies 1 in component "03_FRONT_MOTHERBOARD_BEAM"
ref_plane "工作平面11" through (0, 2.65, 0) normal (0, 1, 0) x (0, 0, 1) in component "03_FRONT_MOTHERBOARD_BEAM"
sketch "草图11" plane through (0, 2.65, 0) normal (0, 1, 0) x (1, 0, 0) in component "03_FRONT_MOTHERBOARD_BEAM"
  circle A0 through (288.35, -192.5, -5.3) (284.825, -190.4648, -5.3) (284.825, -194.5352, -5.3)
extrude "M3 short heat insert for removable front cover (1)" cut sketch "草图11" along normal blind 4.7 contours A0 in plane through (0, -2.65, 0) normal (0, 1, 0) bodies 1 in component "03_FRONT_MOTHERBOARD_BEAM"
ref_plane "工作平面1" through (0, -61.92, 0) normal (0, 1, 0) x (0, 0, 1) in component "06_front_LOW_PSU_RETAINER"
sketch "草图1 (18)" plane through (0, -61.92, 0) normal (0, 1, 0) x (1, 0, 0) in component "06_front_LOW_PSU_RETAINER"
  line L0 (69.4, -30, 123.84) -> (77, -30, 123.84)
  line L1 (77, -30, 123.84) -> (77, -117, 123.84)
  line L2 (77, -117, 123.84) -> (227.8, -117, 123.84)
  line L3 (227.8, -117, 123.84) -> (227.8, -30, 123.84)
  line L4 (227.8, -30, 123.84) -> (235.4, -30, 123.84)
  line L5 (235.4, -30, 123.84) -> (235.4, -125, 123.84)
  line L6 (235.4, -125, 123.84) -> (69.4, -125, 123.84)
  line L7 (69.4, -125, 123.84) -> (69.4, -30, 123.84)
extrude "Low removable PSU retainer" add sketch "草图1 (18)" along normal blind 8 separate body contours L0 L1 L2 L3 L4 L5 L6 L7 in plane through (0, 61.92, 0) normal (0, 1, 0) makes body 22 in component "06_front_LOW_PSU_RETAINER"
ref_plane "工作平面1" through (0, -173.92, 0) normal (0, 1, 0) x (0, 0, 1) in component "06_rear_LOW_PSU_RETAINER"
sketch "草图1 (19)" plane through (0, -173.92, 0) normal (0, 1, 0) x (1, 0, 0) in component "06_rear_LOW_PSU_RETAINER"
  line L0 (69.4, -30, 347.84) -> (77, -30, 347.84)
  line L1 (77, -30, 347.84) -> (77, -117, 347.84)
  line L2 (77, -117, 347.84) -> (227.8, -117, 347.84)
  line L3 (227.8, -117, 347.84) -> (227.8, -30, 347.84)
  line L4 (227.8, -30, 347.84) -> (235.4, -30, 347.84)
  line L5 (235.4, -30, 347.84) -> (235.4, -125, 347.84)
  line L6 (235.4, -125, 347.84) -> (69.4, -125, 347.84)
  line L7 (69.4, -125, 347.84) -> (69.4, -30, 347.84)
extrude "Low removable PSU retainer'" add sketch "草图1 (19)" along normal blind 8 separate body contours L0 L1 L2 L3 L4 L5 L6 L7 in plane through (0, 173.92, 0) normal (0, 1, 0) makes body 23 in component "06_rear_LOW_PSU_RETAINER"
ref_plane "工作平面1" through (0, 0, 30) normal (0, 0, 1) x (1, 0, 0) in component "REF_PSU_FLAT_CENTERED_150x140x86"
sketch "草图1 (20)" plane through (0, 0, 30) normal (0, 0, 1) x (1, 0, 0) in component "REF_PSU_FLAT_CENTERED_150x140x86"
  line L0 (77.4, 51.92) -> (227.4, 51.92)
  line L1 (227.4, 51.92) -> (227.4, 191.92)
  line L2 (227.4, 191.92) -> (77.4, 191.92)
  line L3 (77.4, 191.92) -> (77.4, 51.92)
extrude "Horizontal PSU 150 wide x140 deep x86 high" add sketch "草图1 (20)" along normal blind 86 separate body makes body 24 in component "REF_PSU_FLAT_CENTERED_150x140x86"
ref_plane "工作平面1" through (0, 0, 29.7) normal (0, 0, 1) x (1, 0, 0) in component "REF_PSU_INTAKE_DOWN_MINUS_Z"
sketch "草图1 (21)" plane through (0, 0, 29.7) normal (0, 0, 1) x (1, 0, 0) in component "REF_PSU_INTAKE_DOWN_MINUS_Z"
  circle A0 centre (152.4, 121.92) radius 60
extrude "Downward-facing 120 mm intake marker - approximate" add sketch "草图1 (21)" along normal blind 0.3 separate body makes body 25 in component "REF_PSU_INTAKE_DOWN_MINUS_Z"
ref_plane "工作平面1" through (0, -191.92, 0) normal (0, 1, 0) x (0, 0, 1) in component "REF_PSU_REAR_EXHAUST_PLUS_Y"
sketch "草图1 (22)" plane through (0, -191.92, 0) normal (0, 1, 0) x (1, 0, 0) in component "REF_PSU_REAR_EXHAUST_PLUS_Y"
  line L0 (77.4, -30, 383.84) -> (227.4, -30, 383.84)
  line L1 (227.4, -30, 383.84) -> (227.4, -116, 383.84)
  line L2 (227.4, -116, 383.84) -> (77.4, -116, 383.84)
  line L3 (77.4, -116, 383.84) -> (77.4, -30, 383.84)
extrude "Rear exhaust face direction marker" add sketch "草图1 (22)" along normal blind 0.3 separate body contours L0 L1 L2 L3 in plane through (0, 191.92, 0) normal (0, 1, 0) makes body 26 in component "REF_PSU_REAR_EXHAUST_PLUS_Y"
ref_plane "工作平面2" through (0, 0, 29.9) normal (0, 0, 1) x (1, 0, 0) in component "06_front_LOW_PSU_RETAINER"
sketch "草图2 (12)" plane through (0, 0, 29.9) normal (0, 0, 1) x (1, 0, 0) in component "06_front_LOW_PSU_RETAINER"
  line L0 (60, 50) -> (240, 50)
  line L1 (240, 50) -> (240, 190)
  line L2 (240, 190) -> (60, 190)
  line L3 (60, 190) -> (60, 50)
extrude "Clearance above cradle locating stops" cut sketch "草图2 (12)" along normal blind 6.3 bodies 22 in component "06_front_LOW_PSU_RETAINER"
ref_plane "工作平面2" through (0, 0, 29.9) normal (0, 0, 1) x (1, 0, 0) in component "06_rear_LOW_PSU_RETAINER"
sketch "草图2 (13)" plane through (0, 0, 29.9) normal (0, 0, 1) x (1, 0, 0) in component "06_rear_LOW_PSU_RETAINER"
  line L0 (60, 50) -> (240, 50)
  line L1 (240, 50) -> (240, 190)
  line L2 (240, 190) -> (60, 190)
  line L3 (60, 190) -> (60, 50)
extrude "Clearance above cradle locating stops'" cut sketch "草图2 (13)" along normal blind 6.3 bodies 23 in component "06_rear_LOW_PSU_RETAINER"
ref_plane "工作平面1" through (0, 10, 0) normal (0, 1, 0) x (0, 0, 1) in component "12_front_PCI_SUPPORT_FRAME"
sketch "草图1 (23)" plane through (0, 10, 0) normal (0, 1, 0) x (1, 0, 0) in component "12_front_PCI_SUPPORT_FRAME"
  line L0 (8.45, 0, -20) -> (152.1, 0, -20)
  line L1 (152.1, 0, -20) -> (152.1, -140, -20)
  line L2 (152.1, -140, -20) -> (-4, -140, -20)
  line L3 (-4, -140, -20) -> (8.45, 0, -20)
extrude "Front rear load frame" add sketch "草图1 (23)" along normal blind 16 separate body contours L0 L1 L2 L3 in plane through (0, -10, 0) normal (0, 1, 0) makes body 27 in component "12_front_PCI_SUPPORT_FRAME"
ref_plane "工作平面2" through (0, 0, 16) normal (0, 0, 1) x (1, 0, 0) in component "12_front_PCI_SUPPORT_FRAME"